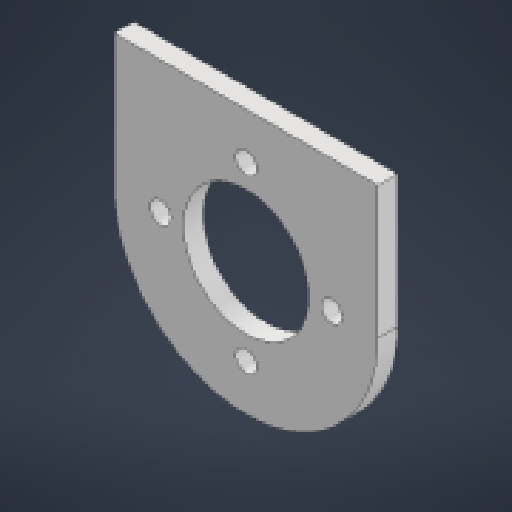
# Autodesk Inventor part: Moter_Fix_Front
Saved by Autodesk Inventor 2027.1 (Build 311270010, 270A)
## iProperties
Created: 2026-11-11
Part Number: Moter_Fix_Front
Material: 一般
Document SubType Name: Modeling
Designer: takuya
Density: 1 g/cm^3
Appearance: 既定
Author: takuya
Autodesk Inventor part; units mm, degrees
ref_plane "YZ Plane" through (0, 0, 0) normal (1, 0, 0) x (0, 1, 0)
ref_plane "XZ Plane" through (0, 0, 0) normal (0, 1, 0) x (-1, 0, 0)
ref_plane "XY Plane" through (0, 0, 0) normal (0, 0, 1) x (1, 0, 0)
sketch "スケッチ1" plane through (0, 0, 0) normal (0, 0, 1) x (1, 0, 0)
  circle A0 centre (0, 0) radius 9.5 projected
  circle A1 centre (13, 0) radius 1.6 projected
  circle A2 centre (0, -13) radius 1.6 projected
  circle A3 centre (-13, 0) radius 1.6 projected
  circle A4 centre (0, 13) radius 1.6 projected
  circle A5 centre (0, 0) radius 16 projected
  circle A6 centre (0, 0) radius 20
  line L0 (20, 0) -> (-20, 0)
  line L1 (-20, 0) -> (-20, 20)
  line L2 (-20, 20) -> (20, 20)
  line L3 (20, 20) -> (20, 0)
  point P0 (0, 0)
  dimension "d0" = 40
  constraints: 8 end point, 2 parallel, 2 point on circle, 1 centre point, 1 coincident, 1 horizontal, 1 perpendicular
  measures "d0" diameter of A6
extrude "押し出し1" add sketch "スケッチ1" along normal blind 3 contours L0 A1 A5 A3 A0 | A0 L0 A3 A5 A1 | L0 A6 A5 | A5 L0 A6 | A6 L2 L3 | L1 L2 A6
sketch "スケッチ2" plane through (0, 0, 3) normal (0, 0, 1) x (1, 0, 0)
  line L0 (20, 0) -> (20, 20) projected
  line L1 (20, 20) -> (-20, 20) projected
  line L2 (-20, 20) -> (-20, 0) projected
  arc A0 (-20, 0) -> (20, 0) centre (0, 0) ccw projected
  circle A1 centre (-13, 0) radius 1.6 projected
  circle A2 centre (0, 0) radius 9.5 projected
  circle A3 centre (0, 13) radius 1.6 projected
  circle A4 centre (0, -13) radius 1.6 projected
  circle A5 centre (13, 0) radius 1.6 projected
  line L3 (20, 0) -> (20, 20) projected
  line L4 (20, 20) -> (13, 20)
  line L5 (13, 20) -> (13, 13)
  line L6 (13, 13) -> (20, 13)
  line L7 (20, 13) -> (20, 20)
  line L8 (-20, 20) -> (-13, 20)
  line L9 (-13, 20) -> (-13, 13)
  line L10 (-13, 13) -> (-20, 13)
  line L11 (-20, 13) -> (-20, 20)
  circle A6 centre (16.5, 16.5) radius 1.5
  circle A7 centre (-16.5, 16.5) radius 1.5
  point P0 (0, 0)
  dimension "d3" = 7
  dimension "d4" = 7
  dimension "d5" = 3
  dimension "d6" = 3
  constraints: 16 end point, 4 parallel, 2 centre point, 2 horizontal, 2 perpendicular, 1 point on line
  measures "d3" distance of L5.end L4.end
  measures "d4" distance of L9.end L10.end
  measures "d5" diameter of A6
  measures "d6" diameter of A7
extrude "押し出し2" cut sketch "スケッチ2" against normal blind 3 contours A6 | A7
